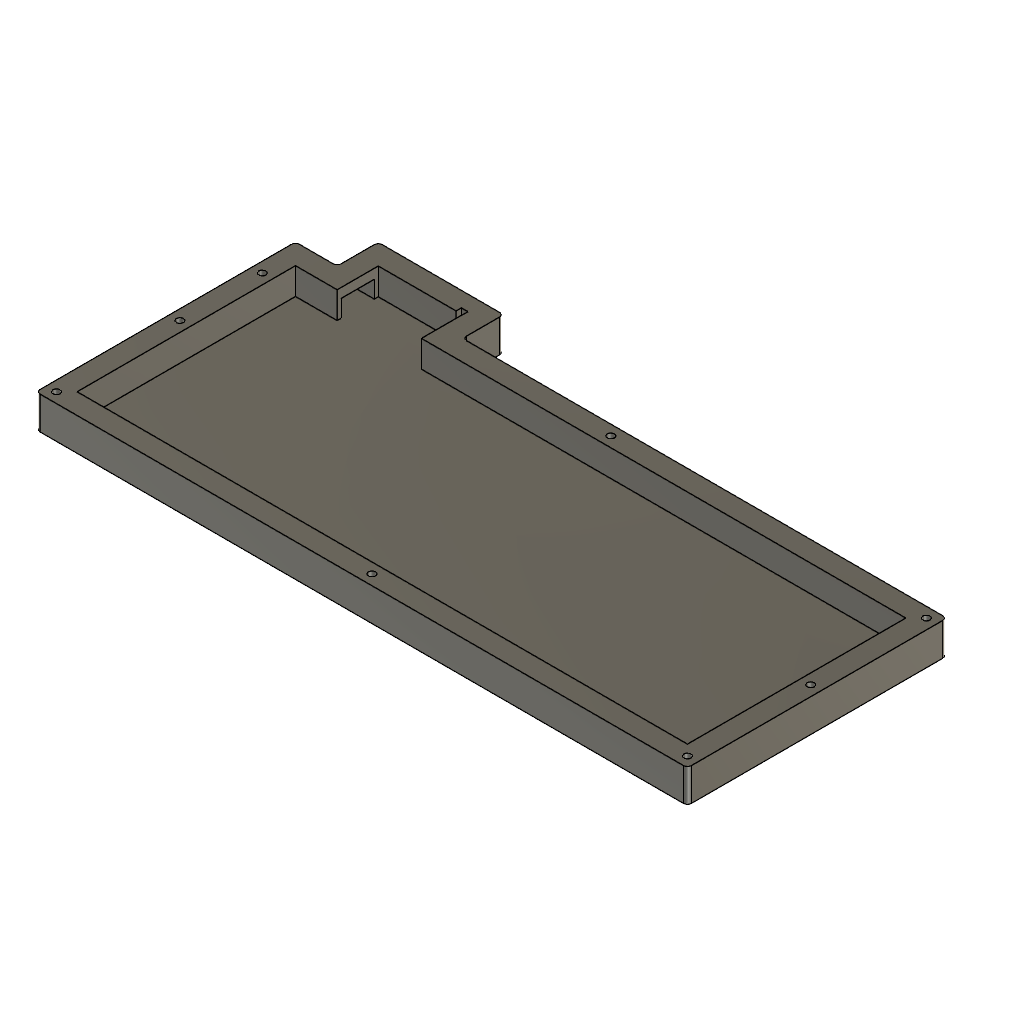
PW67_Lower_Shell_OLED (Autodesk Fusion 360 design; units mm, degrees)
part number: 2026-10-11-22-51-23-929
Autodesk Fusion 360 part; units mm, degrees
sketch "Stepped case outline - measured PCB plus clearance and 10mm flange" plane through (0, 0, 0) normal (0, 0, 1) x (1, 0, 0)
  line L0 (34.35, -164.925) -> (350.85, -164.925)
  line L1 (350.85, -164.925) -> (350.85, -38.85)
  line L2 (350.85, -38.85) -> (115.525, -38.85)
  line L3 (115.525, -38.85) -> (115.525, -18.875)
  line L4 (115.525, -18.875) -> (54.6, -18.875)
  line L5 (54.6, -18.875) -> (54.6, -38.85)
  line L6 (54.6, -38.85) -> (34.35, -38.85)
  line L7 (34.35, -38.85) -> (34.35, -164.925)
extrude "Lower shell blank" add sketch "Stepped case outline - measured PCB plus clearance and 10mm flange" along normal blind 15.9525 from surface at -10.9425
sketch "PCB cavity - 0.4mm per-side clearance" plane through (0, 0, 0) normal (0, 0, 1) x (1, 0, 0)
  line L0 (44.35, -154.925) -> (340.85, -154.925)
  line L1 (340.85, -154.925) -> (340.85, -48.85)
  line L2 (340.85, -48.85) -> (105.525, -48.85)
  line L3 (105.525, -48.85) -> (105.525, -28.875)
  line L4 (105.525, -28.875) -> (64.6, -28.875)
  line L5 (64.6, -28.875) -> (64.6, -48.85)
  line L6 (64.6, -48.85) -> (44.35, -48.85)
  line L7 (44.35, -48.85) -> (44.35, -154.925)
extrude "Electronics cavity and continuous plate bearing ledge" cut sketch "PCB cavity - 0.4mm per-side clearance" along normal blind 12.9525 from surface at -7.9425
sketch "Eight M3 through-bolts - outside PCB" plane through (0, 0, 0) normal (0, 0, 1) x (1, 0, 0)
  circle A0 centre (39.35, -159.925) radius 1.7
  circle A1 centre (192.6, -159.925) radius 1.7
  circle A2 centre (345.85, -159.925) radius 1.7
  circle A3 centre (39.35, -100) radius 1.7
  circle A4 centre (345.85, -100) radius 1.7
  circle A5 centre (39.35, -60) radius 1.7
  circle A6 centre (192.6, -43.85) radius 1.7
  circle A7 centre (345.85, -43.85) radius 1.7
extrude "Aligned 3.4mm through-holes" cut sketch "Eight M3 through-bolts - outside PCB" along normal blind 15.9525 from surface at -10.9425
sketch "USB cable approach corridor - provisional plug envelope" plane through (0, 0, 0) normal (0, 0, 1) x (1, 0, 0)
  line L0 (34.2, -46.8) -> (67.7, -46.8)
  line L1 (67.7, -46.8) -> (67.7, -30.8)
  line L2 (67.7, -30.8) -> (34.2, -30.8)
  line L3 (34.2, -30.8) -> (34.2, -46.8)
extrude "USB-C side access to imported KB2040 connector" cut sketch "USB cable approach corridor - provisional plug envelope" along normal blind 8.3425 from surface at -7.9425
fillet "Rounded exterior corners - prototype" radius 2 10 edges at (34.35, -38.85, -9.4425) (34.35, -164.925, -2.9663) (34.35, -38.85, 2.705) (54.6, -38.85, -9.4425) (54.6, -38.85, 2.705) (54.6, -18.875, -2.9663) (115.525, -18.875, -2.9663) (115.525, -38.85, -2.9663) (350.85, -38.85, -2.9663) (350.85, -164.925, -2.9663)
ref_plane "WorkPlane1" through (0, 0, -7.555) normal (0, 0, 1) x (1, 0, 0)
sketch "OLED cable channel - parametric internal pocket" plane through (0, 0, -7.555) normal (0, 0, 1) x (1, 0, 0)
  line L0 (102.4, -29.5) -> (105.6, -29.5)
  line L1 (105.6, -29.5) -> (105.6, -26.3)
  line L2 (105.6, -26.3) -> (102.4, -26.3)
  line L3 (102.4, -26.3) -> (102.4, -29.5)
  dimension "d304" = 102.4
  dimension "d305" = 29.5
  dimension "d306" = 3.2
  dimension "d307" = 3.2
  constraint horizontal L0
  constraint vertical L1
  constraint horizontal L2
  constraint vertical L3
  measures "d304" horizontal distance of origin L0.start
  measures "d305" vertical distance of origin L0.start
  measures "d306" horizontal distance of L0.start L0.end
  measures "d307" vertical distance of L0.end L1.end
extrude "OLED cable channel - internal only" cut sketch "OLED cable channel - parametric internal pocket" along normal blind 12.565
equation "d13 = caseBottom"
equation "d14 = plateBottom - caseBottom"
equation "d16 = floorZ"
equation "d17 = plateBottom - floorZ"
equation "d31 = caseBottom"
equation "d32 = plateBottom - caseBottom"
equation "d40 = floorZ"
equation "d41 = 0.4 mm - floorZ"
equation "d302 = oledCableChannelBottomZ - 9.855 mm"
equation "d304 = oledCableChannelCenterX - oledCableChannelWidth / 2"
equation "d305 = -oledCableChannelCenterY + oledCableChannelLength / 2"
equation "d306 = oledCableChannelWidth"
equation "d307 = oledCableChannelLength"
equation "d308 = oledCableChannelTopZ - oledCableChannelBottomZ"
equation "pcbTop = 1.51 mm" comment "Measured imported PCB top"
equation "plateTop = pcbTop + 5 mm" comment "ai03 nominal MX plate top above PCB"
equation "plateThickness = 1.5 mm" comment "ai03 MX nominal plate specification"
equation "plateBottom = plateTop - plateThickness" comment "Lower clamp bearing height"
equation "baseThickness = 3 mm" comment "Blueprint starting base thickness"
equation "floorZ = -7.942519737 mm" comment "Replacement KB2040 underside clearance: 0.4 mm, with full 3 mm base thickness"
equation "caseBottom = floorZ - baseThickness" comment "Bottom elevation"
equation "oledCableChannelCenterX = 104 mm" comment "Internal cable riser position"
equation "oledCableChannelCenterY = -27.9 mm" comment "Cable riser ahead of main PCB edge"
equation "oledCableChannelWidth = 3.2 mm" comment "Channel width across X"
equation "oledCableChannelLength = 3.2 mm" comment "Channel span across Y"
equation "oledCableChannelBottomZ = 2.3 mm" comment "Assembly Z; above existing cavity floor"
equation "oledCableChannelTopZ = 14.865 mm" comment "Assembly Z; lower-shell top"
named bodies: "Lower Shell"
